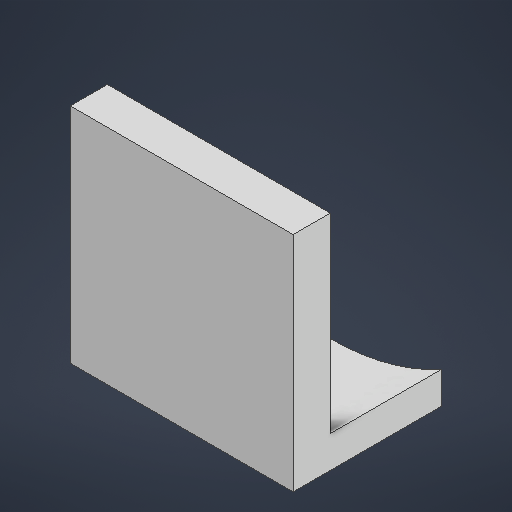
# Autodesk Inventor part: barHoldeript
Saved by Autodesk Inventor 2027.1 (Build 311270010, 270A)
## iProperties
Created: 2026-10-10
Part Number: barHoldeript
Material: Generic
Document SubType Name: Modeling
Designer: khaar
Density: 1 g/cm^3
Appearance: Default
Author: khaar
Autodesk Inventor part; units mm, degrees
ref_plane "YZ Plane" through (0, 0, 0) normal (1, 0, 0) x (0, 1, 0)
ref_plane "XZ Plane" through (0, 0, 0) normal (0, 1, 0) x (-1, 0, 0)
ref_plane "XY Plane" through (0, 0, 0) normal (0, 0, 1) x (1, 0, 0)
sketch "Sketch1" plane through (0, 0, 0) normal (0, 0, 1) x (1, 0, 0)
  line L0 (-15, 15) -> (15, 15)
  line L1 (15, 15) -> (15, -15)
  line L2 (15, -15) -> (-15, -15)
  line L3 (-15, -15) -> (-15, 15)
  line L4 (-15, 15) -> (15, -15) construction
  line L5 (15, 15) -> (-15, -15) construction
  point P0 (0, 0)
  dimension "d0" = 30
  dimension "d1" = 30
  constraints: 12 end point, 2 midpoint, 2 parallel, 1 horizontal, 1 perpendicular
  measures "d0" distance of L0.end L1.end
  measures "d1" distance of L0.start L0.end
extrude "Extrusion1" add sketch "Sketch1" along normal blind 5
sketch "Sketch2" plane through (0, 0, 0) normal (0, 0, -1) x (-1, 0, 0)
  arc A0 (-15.695, -10.2996) -> (15.6385, -10.4208) centre (0.0744, 16.1845) ccw
  line L0 (-15, -15) -> (-15, 15) projected
  line L1 (-15, -10.7013) -> (-15, -15)
  line L2 (-15, -15) -> (14.9864, -15)
  line L3 (14.9864, -15) -> (14.9864, -10.7917)
  constraints: 6 end point, 4 point on circle, 2 perpendicular, 1 centre point, 1 collinear, 1 point on line
extrude "Extrusion3" add sketch "Sketch2" along normal blind 15
body "Solid1"
